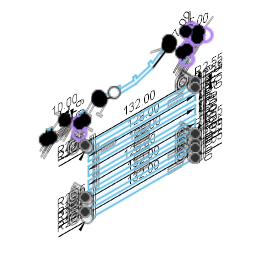
46sp_r2_left (Autodesk Fusion 360 design; units mm, degrees)
Autodesk Fusion 360 part; units mm, degrees
sketch "Sketch_body" plane through (0, 0, 0) normal (1, 0, 0) x (0, 1, 0)
  line L0 (-57.9239, 42.7212) -> (-194.2155, 18.6893)
  line L1 (-28.1683, -14.7541) -> (-42.4304, -4.0068)
  line L2 (-45.4394, -3) -> (-128.1708, -3)
  line L3 (-130.6082, -2.8509) -> (-195.6093, 5.1302)
  arc A0 (-31.8767, 45) -> (-57.9239, 42.7212) centre (-31.8767, -105) ccw
  arc A1 (-28.1683, -14.7541) -> (-25.7686, -15.7236) centre (-25.1592, -10.7609) ccw
  arc A2 (-42.4304, -4.0068) -> (-45.4394, -3) centre (-45.4394, -8) ccw
  arc A3 (-130.6082, -2.8509) -> (-128.1708, -3) centre (-128.1708, 17) ccw
  line L4 (-195.6093, 5.1302) -> (21.9939, -21.5881) construction
  line L5 (-8.7613, -17.8118) -> (-25.7686, -15.7236)
  arc A4 (-8.7613, -17.8118) -> (-3.2843, -13.9917) centre (-8.152, -12.8491) ccw
  line L6 (-195.6093, 5.1302) -> (-197.3656, 5.3459)
  line L7 (-200, 11.7956) -> (-200, 8.3235)
  arc A5 (-200, 8.3235) -> (-197.3656, 5.3459) centre (-197, 8.3235) ccw
  arc A6 (-194.2155, 18.6893) -> (-200, 11.7956) centre (-193, 11.7956) ccw
  line L8 (-31.8767, 45) -> (-2.0562, 45)
  line L9 (-3.2843, -13.9917) -> (7.6792, 32.7148)
  arc A7 (7.6792, 32.7148) -> (-2.0562, 45) centre (-2.0562, 35) ccw
  point P0 (-200, 17.6693)
  point P1 (-200, 5.6693)
  dimension "d171" = 12
  dimension "d216" = 150
  dimension "d218" = 5
  dimension "d219" = 5
  dimension "d220" = 20
  dimension "d229" = 219.2375
  dimension "d230" = 5
  dimension "d233" = 3
  dimension "d234" = 7
  dimension "d263" = 10
  constraint horizontal L2
  constraint tangent L0 A0
  constraint tangent L1 A1
  constraint tangent L2 A2
  constraint tangent L1 A2
  constraint tangent L3 A3
  constraint tangent L2 A3
  constraint coincident P0 L0
  constraint coincident P1 L3
  constraint tangent A1 L5
  constraint tangent L5 A4
  constraint parallel L4 L6
  constraint coincident P1 L6
  constraint tangent L7 A5
  constraint tangent L6 A5
  constraint tangent A0 L8
  constraint horizontal L8
  constraint tangent A4 L9
  constraint tangent L8 A7
  constraint tangent L9 A7
  measures "d171" distance of P0 P1
  measures "d216" radius of A0
  measures "d218" radius of A1
  measures "d219" radius of A2
  measures "d220" radius of A3
  measures "d229" distance of L3.end L4.end
  measures "d230" radius of A4
  measures "d233" radius of A5
  measures "d234" radius of A6
  measures "d263" radius of A7
sketch "Sketch_keypad" plane through (0, 0, 0) normal (1, 0, 0) x (0, 1, 0)
  line L0 (-30, 36.8222) -> (-54.5005, 21.2137)
  line L1 (-54.5005, 21.2137) -> (-52.62, 18.2618)
  line L2 (-28.1195, 33.8704) -> (-30, 36.8222)
  line L3 (-54.5005, 21.2137) -> (-72.6688, 15.4852)
  line L4 (-72.6688, 15.4852) -> (-71.6164, 12.1472)
  line L5 (-71.6164, 12.1472) -> (-53.4481, 17.8757)
  line L6 (-53.4481, 17.8757) -> (-54.5005, 21.2137)
  line L7 (-72.6688, 15.4852) -> (-91.7007, 14.6543)
  line L8 (-91.7007, 14.6543) -> (-91.548, 11.1576)
  line L9 (-91.548, 11.1576) -> (-72.5162, 11.9886)
  line L10 (-72.5162, 11.9886) -> (-72.6688, 15.4852)
  line L11 (-91.7007, 14.6543) -> (-120.0621, 20.9419)
  line L12 (-120.0621, 20.9419) -> (-120.8196, 17.5248)
  line L13 (-120.8196, 17.5248) -> (-92.4582, 11.2373)
  line L14 (-92.4582, 11.2373) -> (-91.7007, 14.6543)
  line L15 (-30, 36.8222) -> (-120.0621, 20.9419) construction
  line L16 (-54.5005, 21.2137) -> (-91.7007, 14.6543) construction
  line L17 (-52.62, 18.2618) -> (-53.4481, 17.8757)
  line L18 (-71.6164, 12.1472) -> (-72.5162, 11.9886)
  line L19 (-91.548, 11.1576) -> (-92.4582, 11.2373)
  line L20 (-120.0621, 20.9419) -> (-115.3589, 37.2783) construction
  line L21 (-30, 36.8222) -> (-39.1341, 51.1599) construction
  line L22 (-39.1341, 51.1599) -> (-115.3589, 37.2783) construction
  line L23 (-72.5162, 11.9886) -> (-71.9927, 0) construction
  line L24 (-71.6164, 12.1472) -> (-68.0079, 0.7026) construction
  line L25 (-68.0079, 0.7026) -> (-71.9927, 0) construction
  circle A0 centre (-53.66, 19.4111) radius 1.55
  circle A1 centre (-72.3235, 13.5266) radius 1.55
  circle A2 centre (-91.874, 12.673) radius 1.55
  line L26 (-30, 36.8222) -> (0, 36.8222) construction
  line L27 (-35.9037, 33.0611) -> (-46.5711, 49.8055) construction
  line L28 (-113.2148, 19.4239) -> (-107.6715, 38.6783) construction
  line L29 (-53.4481, 17.8757) -> (-53.4322, 17.8831)
  line L30 (-28.1195, 33.8704) -> (-52.62, 18.2618)
  circle A3 centre (-31.3073, 35.9894) radius 1.55
  circle A4 centre (-29.4267, 33.0376) radius 1.55
  circle A5 centre (-118.5488, 20.6064) radius 1.55
  circle A6 centre (-119.3064, 17.1894) radius 1.55
  dimension "d15" = 29.05
  dimension "d16" = 3.5
  dimension "d17" = 19.05
  dimension "d18" = 3.5
  dimension "d20" = 3.5
  dimension "d21" = 3.5
  dimension "d22" = 165
  dimension "d23" = 165
  dimension "d24" = 165
  dimension "d26" = 17
  dimension "d27" = 17
  dimension "d28" = 12
  dimension "d30" = 12
  dimension "d37" = 3.1
  dimension "d38" = 3.1
  dimension "d39" = 3.1
  dimension "d56" = 7
  dimension "d58" = 170
  dimension "d85" = 7
  dimension "d90" = 30
  dimension "d270" = 3.1
  dimension "d271" = 3.1
  dimension "d272" = 3.1
  dimension "d273" = 3.1
  constraint perpendicular L0 L1
  constraint parallel L1 L2
  constraint perpendicular L3 L4
  constraint parallel L3 L5
  constraint parallel L4 L6
  constraint perpendicular L7 L8
  constraint parallel L7 L9
  constraint parallel L8 L10
  constraint perpendicular L11 L12
  constraint parallel L11 L13
  constraint parallel L12 L14
  constraint equal L3 L7
  constraint equal L0 L11
  constraint perpendicular L0 L21
  constraint perpendicular L9 L23
  constraint perpendicular L5 L24
  constraint coincident L5.end A0
  constraint coincident L1.end A0
  constraint coincident L9.end A1
  constraint coincident L4.end A1
  constraint coincident L13.end A2
  constraint coincident L8.end A2
  constraint horizontal L26
  constraint coincident L0 L27.start
  constraint coincident L22 L27.end
  constraint perpendicular L0 L27
  constraint coincident L11 L28.start
  constraint coincident L22 L28.end
  constraint parallel L20 L28
  constraint coincident L17 L29.end
  constraint parallel L17 L29
  constraint perpendicular L1 L30
  constraint coincident L0.start A3
  constraint coincident L2.start A4
  constraint coincident L11.end A5
  constraint coincident L12.end A6
  measures "d15" distance of L0.start L0.end
  measures "d16" distance of L0.start L2.start
  measures "d17" distance of L0.end L3.end
  measures "d18" distance of L0.end L5.end
  measures "d20" distance of L3.end L9.end
  measures "d21" distance of L7.end L13.end
  measures "d22" angle of L3 L7
  measures "d23" angle of L0 L3
  measures "d24" angle of L7 L11
  measures "d26" distance of L11.end L20.end
  measures "d27" distance of L0.start L21.end
  measures "d28" distance of L9.end L23.end
  measures "d30" distance of L4.end L24.end
  measures "d37" diameter of A0
  measures "d38" diameter of A1
  measures "d39" diameter of A2
  measures "d56" distance of L21 L27
  measures "d58" angle of L15 L26
  measures "d85" distance of L20 L28
  measures "d90" distance of L0.start L26.end
  measures "d270" diameter of A3
  measures "d271" diameter of A4
  measures "d272" diameter of A5
  measures "d273" diameter of A6
sketch "Sketch_keypad_side" plane through (0, 0, 0) normal (1, 0, 0) x (0, 1, 0)
  line L0 (-28.1195, 33.8704) -> (-30, 36.8222)
  line L1 (-40.3697, 26.0661) -> (-36.6086, 20.1624) construction
  line L2 (-71.6164, 12.1472) -> (-53.4481, 17.8757)
  line L3 (-62.5322, 15.0115) -> (-60.4273, 8.3354) construction
  line L4 (-91.548, 11.1576) -> (-72.5162, 11.9886)
  line L5 (-82.0321, 11.5731) -> (-81.7268, 4.5798) construction
  line L6 (-120.8196, 17.5248) -> (-92.4582, 11.2373)
  line L7 (-106.6389, 14.381) -> (-108.154, 7.547) construction
  line L8 (-36.6086, 20.1624) -> (-23.1195, 28.7559)
  line L9 (-36.6086, 20.1624) -> (-50.0247, 11.6153)
  line L10 (-60.4273, 8.3354) -> (-50.0247, 11.6153)
  line L11 (-60.4273, 8.3354) -> (-70.8298, 5.0555)
  line L12 (-81.7268, 4.5798) -> (-70.8298, 5.0555)
  line L13 (-81.7268, 4.5798) -> (-92.6237, 4.104)
  line L14 (-108.154, 7.547) -> (-92.6237, 4.104)
  line L15 (-108.154, 7.547) -> (-125.8196, 11.4633)
  line L16 (-28.1195, 33.8704) -> (-23.1195, 33.8704) construction
  line L17 (-120.8196, 17.5248) -> (-125.8196, 17.5248) construction
  line L18 (-125.8196, 24.6173) -> (-125.8196, 11.4633)
  line L19 (-30, 36.8222) -> (-120.0621, 20.9419)
  line L20 (-32.6865, 41.0392) -> (-23.1195, 41.0392)
  line L21 (-23.1195, 41.0392) -> (-23.1195, 28.7559)
  line L22 (-32.6865, 41.0392) -> (-125.8196, 24.6173)
  line L23 (-32.6865, 41.0392) -> (83.7533, 41.0392) construction
  line L24 (-92.0091, 11.1289) -> (-92.6237, 4.104) construction
  circle A0 centre (-92.4015, 6.6443) radius 2.55
  line L25 (-72.0543, 12.0001) -> (-70.8298, 5.0555) construction
  circle A1 centre (-71.2726, 7.5668) radius 2.55
  line L26 (-50.0247, 11.6153) -> (-53.034, 18.0688) construction
  circle A2 centre (-51.1024, 13.9264) radius 2.55
  circle A3 centre (-25.6695, 28.7559) radius 2.55
  circle A4 centre (-123.2696, 24.6173) radius 2.55
  circle A5 centre (-123.2696, 11.4633) radius 2.55
  line L27 (-32.6865, 41.0392) -> (-32.242, 35.9586)
  line L28 (-32.6865, 41.0392) -> (-27.5865, 41.0392) construction
  circle A6 centre (-32.4643, 38.4989) radius 2.55
  line L29 (-30, 36.8222) -> (-28.1195, 33.8704)
  line L30 (-30.734, 32.2047) -> (-52.62, 18.2618)
  line L31 (-53.4481, 17.8757) -> (-71.6164, 12.1472)
  line L32 (-72.5162, 11.9886) -> (-91.548, 11.1576)
  line L33 (-92.4582, 11.2373) -> (-117.7931, 16.8539)
  line L34 (-120.0621, 20.9419) -> (-120.8196, 17.5248)
  line L35 (-117.0356, 20.2709) -> (-91.7007, 14.6543)
  line L36 (-91.7007, 14.6543) -> (-72.6688, 15.4852)
  line L37 (-72.6688, 15.4852) -> (-54.5005, 21.2137)
  line L38 (-54.5005, 21.2137) -> (-32.6145, 35.1566)
  arc A7 (-30, 36.8222) -> (-32.6145, 35.1566) centre (-31.3073, 35.9894) ccw
  arc A8 (-30.734, 32.2047) -> (-28.1195, 33.8704) centre (-29.4267, 33.0376) ccw
  arc A9 (-53.4481, 17.8757) -> (-52.62, 18.2618) centre (-53.66, 19.4111) ccw
  arc A10 (-72.5162, 11.9886) -> (-71.6164, 12.1472) centre (-72.3235, 13.5266) ccw
  arc A11 (-92.4582, 11.2373) -> (-91.548, 11.1576) centre (-91.874, 12.673) ccw
  arc A12 (-117.0356, 20.2709) -> (-120.0621, 20.9419) centre (-118.5488, 20.6064) ccw
  arc A13 (-120.8196, 17.5248) -> (-117.7931, 16.8539) centre (-119.3064, 17.1894) ccw
  line L39 (-23.1195, 41.0392) -> (-26.7257, 37.433) construction
  circle A14 centre (-24.9226, 39.2361) radius 2.55
  point P0 (-91.7007, 14.6543)
  point P1 (-72.6688, 15.4852)
  point P2 (-54.5005, 21.2137)
  point P3 (-31.3073, 35.9894)
  point P4 (-29.4267, 33.0376)
  point P5 (-53.66, 19.4111)
  point P6 (-72.3235, 13.5266)
  point P7 (-91.874, 12.673)
  point P8 (-119.3064, 17.1894)
  point P9 (-118.5488, 20.6064)
  dimension "d93" = 7
  dimension "d94" = 7
  dimension "d95" = 7
  dimension "d96" = 7
  dimension "d100" = 5
  dimension "d101" = 5
  dimension "d104" = 5
  dimension "d107" = 170
  dimension "d129" = 5.1
  dimension "d130" = 5.1
  dimension "d131" = 5.1
  dimension "d137" = 5.1
  dimension "d139" = 5.1
  dimension "d140" = 5.1
  dimension "d141" = 85
  dimension "d142" = 5.1
  dimension "d372" = 5.1
  dimension "d373" = 45
  constraint midpoint L2 L3.start
  constraint perpendicular L2 L3
  constraint midpoint L4 L5.start
  constraint perpendicular L4 L5
  constraint midpoint L6 L7.start
  constraint perpendicular L6 L7
  constraint perpendicular L1 L9
  constraint perpendicular L3 L10
  constraint perpendicular L3 L11
  constraint perpendicular L5 L12
  constraint perpendicular L5 L13
  constraint perpendicular L7 L14
  constraint perpendicular L7 L15
  constraint horizontal L16
  constraint coincident L6.start L17.start
  constraint horizontal L17
  constraint horizontal L20
  constraint perpendicular L20 L21
  constraint horizontal L23
  constraint vertical L18
  constraint coincident L4.start L32.end
  constraint coincident L13.end A0
  constraint coincident L11.end A1
  constraint coincident L2.end L31.start
  constraint coincident L9.end A2
  constraint coincident L8.end A3
  constraint coincident L18.start A4
  constraint coincident L15.end A5
  constraint horizontal L28
  constraint coincident L27.end A6
  constraint coincident L20.start A6
  constraint coincident L0.end L19.start
  constraint coincident L30.end A9.end
  constraint coincident L2.start L31.end
  constraint coincident L4.end L32.start
  constraint coincident L6.end L33.start
  constraint coincident L19.end L34.start
  constraint coincident P0 L35.end
  constraint coincident P1 L36.end
  constraint coincident P2 L37.end
  constraint coincident P3 A7.centre
  constraint tangent L0 A7
  constraint coincident P4 A8.centre
  constraint tangent L0 A8
  constraint coincident P5 A9.centre
  constraint coincident P6 A10.centre
  constraint coincident P7 A11.centre
  constraint coincident P8 A13.centre
  constraint coincident P9 A12.centre
  constraint coincident L19.end A12
  constraint coincident A10 L25.start
  constraint coincident A11 L24.start
  constraint coincident L6 L33.end
  constraint coincident L39.end A14
  constraint coincident L20.end A14
  measures "d93" distance of L1.start L1.end
  measures "d94" distance of L3.start L3.end
  measures "d95" distance of L5.start L5.end
  measures "d96" distance of L7.start L7.end
  measures "d100" distance of L0.start L16.end
  measures "d101" distance of L6.start L17.end
  measures "d104" distance of L0.end L20.start
  measures "d107" angle of L22 L23
  measures "d129" diameter of A0
  measures "d130" diameter of A1
  measures "d131" diameter of A2
  measures "d137" diameter of A3
  measures "d139" diameter of A4
  measures "d140" diameter of A5
  measures "d141" angle of L27 L28
  measures "d142" distance of L20.start L27.end
  measures "d372" distance of L20.end L39.end
  measures "d373" angle of L21 L39
extrude "Extrude1" add sketch "Sketch_keypad" along normal mid plane 130 contours L0 A3 | L0 L1 L2 A0 L30 A3 A4 | L30 A4 | L3 L4 L5 L6 A0 A1 | L1 L6 A0 | L1 A0 | L1 L6 L17 A0 L29 | L7 L8 L9 L10 A1 A2 | L4 L10 A1 | L6 A0 | L4 A1 | L4 L10 L18 A1 | L11 L12 L13 L14 A2 A5 A6 | L8 L14 A2 | L10 A1 | L8 A2 | L8 L14 L19 A2 | L11 A5 | L14 A2 | L13 A6 picked at (-30.7698, 35.237) picked at (-29.3326, 33.6055) picked at (-118.8071, 19.7503) picked at (-119.7522, 17.836) makes body 1 in component "keypad"
extrude "Extrude1'" add sketch "Sketch_keypad_side" along normal blind 4 from surface at 60 separate body contours L0 L2 L4 L6 L19 A6 L29 L30 L31 L32 L33 L34 L35 L36 L37 L38 A7 A8 A9 A10 A11 A12 | L0 L2 L4 L6 L8 L9 L10 L11 L12 L13 L14 L15 L18 L19 L20 L21 L22 A0 A1 A2 A3 A4 A5 A6 L29 L30 L31 L32 L33 L34 A7 A8 A9 A10 A11 A12 A13 A14 | L19 A6 A7 | L19 L27 A6 | L19 L27 A6 A7 | L20 L27 A6 A7 | L19 L27 A6 A7 | L19 L27 A7 | L19 L22 L27 A6 A7 | L19 A6 A7 | L19 A6 L35 L36 L37 L38 A7 A12 | L20 L21 A14 | L19 A12 | L22 A4 | L8 A3 | L6 A13 | L15 A5 | L9 L10 A2 | L13 L14 A0 | L11 L12 A1 picked at (-124.0002, 23.7613) picked at (-26.2353, 29.6312) picked at (-122.4553, 11.4729) makes body 2 in component "keypad_side_r"
extrude "Extrude1''" add sketch "Sketch_keypad_side" against normal blind 4 from surface at -60 separate body contours L0 L2 L4 L6 L19 A6 L29 L30 L31 L32 L33 L34 L35 L36 L37 L38 A7 A8 A9 A10 A11 A12 | L0 L2 L4 L6 L8 L9 L10 L11 L12 L13 L14 L15 L18 L19 L20 L21 L22 A0 A1 A2 A3 A4 A5 A6 L29 L30 L31 L32 L33 L34 A7 A8 A9 A10 A11 A12 A13 A14 | L19 A6 A7 | L19 L27 A6 | L19 L27 A6 A7 | L20 L27 A6 A7 | L19 L27 A6 A7 | L19 L27 A7 | L19 L22 L27 A6 A7 | L19 A6 A7 | L19 A6 L35 L36 L37 L38 A7 A12 | L20 L21 A14 | L19 A12 | L22 A4 | L8 A3 | L6 A13 | L15 A5 | L9 L10 A2 | L13 L14 A0 | L11 L12 A1 picked at (-124.0002, 23.7613) picked at (-26.2353, 29.6312) picked at (-122.4553, 11.4729) makes body 3 in component "keypad_side_l"
extrude "Extrude2" cut sketch "Sketch_keypad" along normal through all bodies 2 in component "keypad_side_r"
extrude "Extrude2'" cut sketch "Sketch_keypad" against normal through all bodies 3 in component "keypad_side_l"
extrude "Extrude1'''" add sketch "Sketch_body" along normal blind 12 from surface at 60 separate body makes body 4 in component "body_side_r"
extrude "Extrude1''''" add sketch "Sketch_body" against normal blind 12 from surface at -60 separate body makes body 5 in component "body_side_l"
extrude "Extrude2''" cut sketch "Sketch_keypad_side" against normal blind 6 from surface at -60 contours L0 L2 L4 L6 L19 A6 L29 L30 L31 L32 L33 L34 L35 L36 L37 L38 A7 A8 A9 A10 A11 A12 | L0 L2 L4 L6 L8 L9 L10 L11 L12 L13 L14 L15 L18 L19 L20 L21 L22 A0 A1 A2 A3 A4 A5 A6 L29 L30 L31 L32 L33 L34 A7 A8 A9 A10 A11 A12 A13 A14 | L19 A6 A7 | L19 L27 A6 | L19 L27 A6 A7 | L20 L27 A6 A7 | L19 L27 A6 A7 | L19 L27 A7 | L19 L22 L27 A6 A7 | L19 A6 A7 | L19 A6 L35 L36 L37 L38 A7 A12 | L20 A6 | L22 A6 | L20 A14 | L20 L21 A14 | L19 A12 | L21 A14 | L22 A4 | L22 A4 | L8 A3 | L8 A3 | L6 A13 | L15 A5 | L15 A5 | L9 L10 A2 | L13 L14 A0 | L11 L12 A1 bodies 5 in component "body_side_l"
extrude "Extrude2'''" cut sketch "Sketch_keypad_side" along normal blind 6 from surface at 60 contours L0 L2 L4 L6 L19 A6 L29 L30 L31 L32 L33 L34 L35 L36 L37 L38 A7 A8 A9 A10 A11 A12 | L0 L2 L4 L6 L8 L9 L10 L11 L12 L13 L14 L15 L18 L19 L20 L21 L22 A0 A1 A2 A3 A4 A5 A6 L29 L30 L31 L32 L33 L34 A7 A8 A9 A10 A11 A12 A13 A14 | L19 A6 A7 | L19 L27 A6 | L19 L27 A6 A7 | L20 L27 A6 A7 | L19 L27 A6 A7 | L19 L27 A7 | L19 L22 L27 A6 A7 | L19 A6 A7 | L19 A6 L35 L36 L37 L38 A7 A12 | L20 A6 | L22 A6 | L20 A14 | L20 L21 A14 | L19 A12 | L21 A14 | L22 A4 | L22 A4 | L8 A3 | L8 A3 | L6 A13 | L15 A5 | L15 A5 | L9 L10 A2 | L13 L14 A0 | L11 L12 A1 bodies 4 in component "body_side_r"
sketch "Sketch_inside" plane through (0, 0, 0) normal (1, 0, 0) x (0, 1, 0)
  line L0 (-22.5454, 31.493) -> (-11.2426, 31.493)
  line L1 (-7, 27.2504) -> (-7, 12)
  line L2 (-200, 11.7956) -> (-200, 10.0967)
  line L3 (-195.6052, 5.1335) -> (-193.8472, 4.9191)
  arc A0 (-194.2155, 18.6893) -> (-200, 11.7956) centre (-193, 11.7956) ccw
  arc A1 (-200, 10.0967) -> (-195.6052, 5.1335) centre (-195, 10.0967) ccw
  arc A2 (-159.5313, 0.7351) -> (-147.4283, 0) centre (-147.4283, 100) ccw
  line L4 (-200, 17.6693) -> (-57.9239, 42.7212) construction
  line L5 (-113.2159, 19.4201) -> (-113.2148, 19.4239)
  line L6 (33, 43) -> (-50.411, 43) construction
  line L7 (-10.9159, 43) -> (-29.4045, 43)
  arc A3 (3.5832, 24.1561) -> (-10.9159, 43) centre (-10.9159, 28) ccw
  arc A4 (-29.4045, 43) -> (-35.7906, 33.1332) centre (-29.4045, 36) ccw
  line L8 (-120.8196, 17.5248) -> (-120.0621, 20.9419)
  line L9 (-117.0356, 20.2709) -> (-113.2148, 19.4239)
  line L10 (-113.2148, 19.4238) -> (-113.2148, 19.4239)
  arc A5 (-120.8196, 17.5248) -> (-117.7931, 16.8539) centre (-119.3064, 17.1894) ccw
  arc A6 (-117.0356, 20.2709) -> (-120.0621, 20.9419) centre (-118.5488, 20.6064) ccw
  line L11 (-27, 12) -> (-16, 12)
  line L12 (-10, 12) -> (-7, 12)
  line L13 (-35.7906, 33.1332) -> (-31.8487, 35.6445)
  line L14 (-29.9682, 32.6926) -> (-31.4653, 31.7388)
  line L15 (-30, 36.8222) -> (-30.671, 33.7957) construction
  line L16 (-28.1195, 33.8704) -> (-31.146, 34.5413) construction
  arc A7 (-28.7989, 35.5125) -> (-31.8487, 35.6445) centre (-30.3355, 35.309) ccw
  arc A8 (-29.9682, 32.6926) -> (-28.7989, 35.5125) centre (-29.6327, 34.2059) ccw
  line L17 (-138.8196, 0) -> (-147.4283, 0)
  line L18 (-159.5313, 0.7351) -> (-173.1985, 2.4015)
  line L19 (3.583, 24.1551) -> (3.5832, 24.1561)
  line L20 (-194.2155, 18.6893) -> (-120.7062, 29.0203)
  line L21 (-113.2148, 19.4239) -> (-113.0052, 20.1518)
  arc A9 (-113.0052, 20.1518) -> (-120.7062, 29.0203) centre (-119.732, 22.0885) ccw
  line L22 (-20, 3) -> (-20, -2)
  line L23 (-17, -5) -> (-14.6617, -5)
  arc A10 (-20, -2) -> (-17, -5) centre (-17, -2) ccw
  arc A11 (-14.6617, -5) -> (-0.0565, 6.5812) centre (-14.6617, 10) ccw
  line L24 (-195.6093, 5.1302) -> (21.9939, -21.5881) construction
  line L25 (-27, 12) -> (-27, 3)
  line L26 (2.3012, 18.2936) -> (-0.0565, 6.5812)
  line L27 (2.0211, 16.9023) -> (-7, 18.01)
  line L28 (-7, 12) -> (0.8405, 11.0373)
  line L29 (-127.8196, 3) -> (-127.8196, 0)
  line L30 (-127.8196, 0) -> (-132.8196, 0)
  line L31 (-27, 3) -> (-20, 3)
  line L32 (-27, 3) -> (-120.8196, 3) construction
  line L33 (-120.8196, 10.8902) -> (-120.8196, 3)
  line L34 (-120.8196, 3) -> (-127.8196, 3)
  line L35 (-3.2843, -13.9917) -> (7.6792, 32.7148)
  line L36 (-161.2696, 9) -> (-151.3696, 9)
  line L37 (-148.8196, 11.55) -> (-148.8196, 12.45)
  line L38 (-151.3696, 15) -> (-161.2696, 15)
  line L39 (-163.8196, 12.45) -> (-163.8196, 11.55)
  line L40 (-163.8196, 9) -> (-148.8196, 15) construction
  line L41 (-148.8196, 9) -> (-163.8196, 15) construction
  arc A12 (-148.8196, 12.45) -> (-151.3696, 15) centre (-151.3696, 12.45) ccw
  arc A13 (-151.3696, 9) -> (-148.8196, 11.55) centre (-151.3696, 11.55) ccw
  arc A14 (-161.2696, 15) -> (-163.8196, 12.45) centre (-161.2696, 12.45) ccw
  arc A15 (-163.8196, 11.55) -> (-161.2696, 9) centre (-161.2696, 11.55) ccw
  line L42 (-138.8196, 0) -> (-132.8196, 0)
  line L43 (-132.8196, 0) -> (-132.8196, 10)
  line L44 (-135.3696, 12.55) -> (-136.2696, 12.55)
  line L45 (-138.8196, 10) -> (-138.8196, 0)
  arc A16 (-132.8196, 10) -> (-135.3696, 12.55) centre (-135.3696, 10) ccw
  arc A17 (-136.2696, 12.55) -> (-138.8196, 10) centre (-136.2696, 10) ccw
  line L46 (-132.8196, 0) -> (-138.8196, 0)
  line L47 (-138.8196, 0) -> (-138.8196, -10)
  line L48 (-138.8196, -10) -> (-132.8196, -10)
  line L49 (-132.8196, -10) -> (-132.8196, 0)
  line L50 (-179.1544, 3.1277) -> (-173.1985, 2.4015)
  line L51 (-173.1985, 2.4015) -> (-171.9882, 12.328)
  line L52 (-174.2108, 15.1679) -> (-175.1042, 15.2768)
  line L53 (-177.9441, 13.0542) -> (-179.1544, 3.1277)
  arc A18 (-175.1042, 15.2768) -> (-177.9441, 13.0542) centre (-175.4128, 12.7455) ccw
  arc A19 (-171.9882, 12.328) -> (-174.2108, 15.1679) centre (-174.5194, 12.6366) ccw
  line L54 (-179.1544, 3.1277) -> (-173.1985, 2.4015)
  line L55 (-173.1985, 2.4015) -> (-174.4088, -7.525)
  line L56 (-174.4088, -7.525) -> (-180.3647, -6.7988)
  line L57 (-180.3647, -6.7988) -> (-179.1544, 3.1277)
  line L58 (-179.1544, 3.1277) -> (-193.8472, 4.9191)
  line L59 (3.583, 24.1551) -> (2.3012, 18.2936)
  line L60 (2.3012, 18.2936) -> (-2.5834, 19.3617)
  line L61 (-4.5297, 22.3976) -> (-4.3375, 23.2768)
  line L62 (-1.3016, 25.2232) -> (3.583, 24.1551)
  arc A20 (-1.3016, 25.2232) -> (-4.3375, 23.2768) centre (-1.8463, 22.7321) ccw
  arc A21 (-4.5297, 22.3976) -> (-2.5834, 19.3617) centre (-2.0386, 21.8529) ccw
  line L63 (-10, 12) -> (-16, 12)
  line L64 (-16, 12) -> (-16, 2)
  line L65 (-13.45, -0.55) -> (-12.55, -0.55)
  line L66 (-10, 2) -> (-10, 12)
  arc A22 (-12.55, -0.55) -> (-10, 2) centre (-12.55, 2) ccw
  arc A23 (-16, 2) -> (-13.45, -0.55) centre (-13.45, 2) ccw
  line L67 (-7, 27.2504) -> (-11.2426, 31.493)
  line L68 (-11.2426, 31.493) -> (-8.454, 34.2817)
  line L69 (-4.2113, 30.039) -> (-7, 27.2504)
  line L70 (-5.904, 36.8317) -> (-5.904, 31.7317) construction
  line L71 (-1.6613, 32.589) -> (-6.7613, 32.589) construction
  arc A24 (-4.2113, 30.039) -> (-3.4655, 35.0275) centre (-4.2113, 32.589) ccw
  arc A25 (-3.4655, 35.0275) -> (-8.454, 34.2817) centre (-5.904, 34.2817) ccw
  line L72 (-7, 27.2504) -> (-11.2426, 31.493)
  line L73 (-11.2426, 31.493) -> (-16.1924, 26.5433)
  line L74 (-16.1924, 26.5433) -> (-11.9497, 22.3006)
  line L75 (-11.9497, 22.3006) -> (-7, 27.2504)
  line L76 (-10, 12) -> (-16, 12)
  line L77 (-16, 12) -> (-16, 27)
  line L78 (-16, 27) -> (-10, 27)
  line L79 (-10, 27) -> (-10, 12)
  line L80 (3.583, 24.1551) -> (2.3012, 18.2936)
  line L81 (2.3012, 18.2936) -> (12.0704, 16.1573)
  line L82 (12.0704, 16.1573) -> (13.3521, 22.0188)
  line L83 (13.3521, 22.0188) -> (3.583, 24.1551)
  line L84 (-68.0079, 0.7026) -> (-68.0079, 1)
  line L85 (-120.0621, 20.9419) -> (-72.6688, 15.4852) construction
  line L86 (-72.6688, 15.4852) -> (-77.7808, 31.6984) construction
  line L87 (-71.6164, 12.1472) -> (-68.0079, 0.7026)
  line L88 (-72.6688, 15.4852) -> (-91.7007, 14.6543)
  line L89 (-73.186, 15.4627) -> (-74.5406, 19.7589)
  line L90 (-73.186, 15.4627) -> (-91.7007, 14.6543)
  line L91 (-91.7007, 14.6543) -> (-113.2148, 19.4239)
  line L92 (-119.3304, 29.0885) -> (-80.4159, 24.6081)
  arc A26 (-74.5406, 19.7589) -> (-80.4159, 24.6081) centre (-81.2166, 17.654) ccw
  line L93 (-32.3836, 27.5967) -> (-31.309, 25.91)
  line L94 (-31.309, 25.91) -> (-22.5454, 31.493)
  line L95 (-32.3836, 27.5967) -> (-29.8534, 29.2086)
  line L96 (-29.8534, 29.2086) -> (-31.4653, 31.7388)
  line L97 (-117.7931, 16.8539) -> (-115.8405, 16.421)
  line L98 (-113.561, 12.8428) -> (-113.9938, 10.8902)
  line L99 (-113.9938, 10.8902) -> (-120.8196, 10.8902)
  line L100 (-113.561, 12.8428) -> (-116.4898, 13.4921)
  line L101 (-116.4898, 13.4921) -> (-115.8405, 16.421)
  point P0 (-200, 17.6693)
  point P1 (-120.8196, 17.5248)
  point P2 (-127.8196, 0)
  point P3 (-200, 5.6693)
  point P4 (-57.9239, 42.7212)
  point P5 (-30, 36.8222)
  point P6 (-28.1195, 33.8704)
  point P7 (-156.3196, 12)
  point P8 (-20, -5)
  point P9 (-194.2155, 18.6893)
  point P10 (-156.3196, 12)
  point P11 (-138.8196, 12.55)
  point P12 (-177.6354, 15.5854)
  point P13 (-3.7927, 25.768)
  point P14 (-10, -0.55)
  point P15 (-68.0079, 0.7026)
  point P16 (-72.6688, 15.4852)
  dimension "d169" = 12
  dimension "d235" = 7
  dimension "d236" = 5
  dimension "d237" = 100
  dimension "d261" = 15
  dimension "d262" = 7
  dimension "d290" = 3.1
  dimension "d291" = 3.1
  dimension "d331" = 2
  dimension "d333" = 7
  dimension "d335" = 3
  dimension "d336" = 15
  dimension "d352" = 9
  dimension "d374" = 15
  dimension "d375" = 6
  dimension "d376" = 2.55
  dimension "d377" = 2.55
  dimension "d378" = 2.55
  dimension "d379" = 2.55
  dimension "d380" = 6
  dimension "d381" = 12.55
  dimension "d382" = 2.55
  dimension "d383" = 2.55
  dimension "d384" = 10
  dimension "d385" = 6
  dimension "d386" = 12.55
  dimension "d387" = 2.55
  dimension "d388" = 2.55
  dimension "d389" = 10
  dimension "d390" = 6
  dimension "d391" = 7.55
  dimension "d392" = 2.55
  dimension "d393" = 2.55
  dimension "d396" = 12.55
  dimension "d397" = 2.55
  dimension "d398" = 2.55
  dimension "d399" = 6
  dimension "d402" = 5.1
  dimension "d403" = 5.1
  dimension "d404" = 45
  dimension "d405" = 45
  dimension "d406" = 7
  dimension "d407" = 15
  dimension "d408" = 10
  dimension "d421" = 17
  dimension "d424" = 0.5
  dimension "d425" = 7
  dimension "d462" = 3
  dimension "d467" = 3
  constraint coincident P1 L8.start
  constraint horizontal L0
  constraint perpendicular L1 L11
  constraint coincident P3 L18
  constraint vertical L2
  constraint parallel L3 L18
  constraint tangent L2 A0
  constraint tangent L2 A1
  constraint tangent L3 A1
  constraint tangent A2 L18
  constraint coincident P0 L4.start
  constraint coincident P4 L4.end
  constraint tangent L7 A3
  constraint tangent L7 A4
  constraint coincident L8.end A6.end
  constraint coincident L8.end A6
  constraint coincident P1 A5
  constraint coincident L12.start L11
  constraint collinear L11 L12
  constraint coincident L15.end A7
  constraint coincident P5 A7
  constraint tangent L21 A9
  constraint tangent L20 A9
  constraint perpendicular L22 L23
  constraint coincident P8 L22
  constraint coincident P8 L23
  constraint tangent L22 A10
  constraint tangent L23 A10
  constraint tangent L23 A11
  constraint coincident L1 L27.end
  constraint perpendicular L11 L25
  constraint coincident L26 L27.start
  constraint coincident L26 L28.end
  constraint coincident P2 L29.end
  constraint perpendicular L25 L31
  constraint perpendicular L29 L32
  constraint perpendicular L32 L33
  constraint vertical L33
  constraint horizontal L36
  constraint perpendicular L36 L37
  constraint parallel L36 L38
  constraint parallel L37 L39
  constraint coincident L40 P10
  constraint coincident L41 P10
  constraint coincident P10 P7
  constraint coincident L40.end L38
  constraint coincident L40.end L37
  constraint tangent L38 A12
  constraint tangent L37 A12
  constraint coincident L41.start L36
  constraint coincident L41.start L37
  constraint tangent L36 A13
  constraint tangent L37 A13
  constraint coincident L41.end L38
  constraint coincident L41.end L39
  constraint tangent L38 A14
  constraint tangent L39 A14
  constraint coincident L40.start L39
  constraint coincident L40.start L36
  constraint tangent L39 A15
  constraint tangent L36 A15
  constraint horizontal L42
  constraint vertical L43
  constraint horizontal L44
  constraint vertical L45
  constraint tangent L44 A16
  constraint tangent L43 A16
  constraint coincident P11 L44
  constraint coincident P11 L45
  constraint tangent L44 A17
  constraint tangent L45 A17
  constraint horizontal L46
  constraint vertical L47
  constraint horizontal L48
  constraint vertical L49
  constraint perpendicular L50 L51
  constraint parallel L50 L52
  constraint parallel L51 L53
  constraint coincident P12 L52
  constraint coincident P12 L53
  constraint tangent L52 A18
  constraint tangent L53 A18
  constraint tangent L51 A19
  constraint tangent L52 A19
  constraint perpendicular L54 L55
  constraint parallel L54 L56
  constraint parallel L55 L57
  constraint perpendicular L53 L58
  constraint perpendicular L59 L60
  constraint parallel L59 L61
  constraint parallel L60 L62
  constraint coincident P13 L61
  constraint coincident P13 L62
  constraint tangent L61 A20
  constraint tangent L62 A20
  constraint tangent L60 A21
  constraint tangent L61 A21
  constraint perpendicular L19 L62
  constraint perpendicular L63 L64
  constraint parallel L63 L65
  constraint parallel L64 L66
  constraint coincident P14 L65
  constraint coincident P14 L66
  constraint tangent L65 A22
  constraint tangent L66 A22
  constraint tangent L64 A23
  constraint tangent L65 A23
  constraint vertical L1
  constraint perpendicular L67 L68
  constraint parallel L68 L69
  constraint coincident L70.end A25
  constraint coincident L70.start A25
  constraint perpendicular L72 L73
  constraint parallel L72 L74
  constraint parallel L73 L75
  constraint perpendicular L76 L77
  constraint parallel L76 L78
  constraint parallel L77 L79
  constraint perpendicular L80 L81
  constraint parallel L80 L82
  constraint parallel L81 L83
  constraint coincident P15 L84.start
  constraint perpendicular L32 L84
  constraint coincident P16 L85.end
  constraint parallel L86 L87
  constraint coincident L88 L89.start
  constraint parallel L86 L89
  constraint coincident L88.end L90.end
  constraint parallel L9 L91
  constraint tangent A9 L92
  constraint tangent L89 A26
  constraint tangent L92 A26
  constraint perpendicular L14 L93
  constraint perpendicular L93 L94
  constraint perpendicular L93 L95
  constraint perpendicular L14 L96
  constraint perpendicular L97 L98
  constraint perpendicular L33 L99
  constraint perpendicular L97 L101
  measures "d169" distance of P0 P3
  measures "d235" radius of A0
  measures "d236" radius of A1
  measures "d237" radius of A2
  measures "d261" radius of A3
  measures "d262" radius of A4
  measures "d290" distance of P5 L15.end
  measures "d291" distance of P6 L16.end
  measures "d331" angle of L4 L20
  measures "d333" radius of A9
  measures "d335" radius of A10
  measures "d336" radius of A11
  measures "d352" distance of L11.start L25.end
  measures "d374" distance of L40.end L41.end
  measures "d375" distance of L41.start L40.end
  measures "d376" radius of A12
  measures "d377" radius of A13
  measures "d378" radius of A14
  measures "d379" radius of A15
  measures "d380" distance of L17.start L30.end
  measures "d381" distance of L17.start P11
  measures "d382" radius of A16
  measures "d383" radius of A17
  measures "d384" distance of L30.end L48.end
  measures "d385" distance of L50.start L18.end
  measures "d386" distance of L50.start P12
  measures "d387" radius of A18
  measures "d388" radius of A19
  measures "d389" distance of L50.start L56.end
  measures "d390" distance of L19.start L26.start
  measures "d391" distance of L19.start P13
  measures "d392" radius of A20
  measures "d393" radius of A21
  measures "d396" distance of L12.start P14
  measures "d397" radius of A22
  measures "d398" radius of A23
  measures "d399" distance of L1.start L0.end
  measures "d401" distance of L1.start L71.start
  measures "d402" distance of L70.start L70.end
  measures "d403" distance of L71.start L71.end
  measures "d404" angle of L69 L71
  measures "d405" angle of L68 L70
  measures "d406" distance of L1.start L74.end
  measures "d407" distance of L12.start L78.end
  measures "d408" distance of L19.start L82.end
  measures "d421" distance of P16 L86.end
  measures "d424" distance of L86 L89
  measures "d425" radius of A26
  measures "d462" distance of L93.start L95.end
  measures "d467" distance of L98.start L100.end
extrude "Extrude1'''''" add sketch "Sketch_inside" along normal mid plane 120 separate body contours L0 L1 L7 A3 A4 L13 L14 A7 A8 L26 L27 L60 L61 L62 A20 A21 L68 L69 A24 A25 L93 L94 L95 L96 | L1 L26 L27 L28 | L11 L12 L22 L23 A10 A11 L25 L26 L28 L31 L64 L65 L66 A22 A23 | L2 L3 A0 A1 A2 L8 L9 A5 A6 L17 L18 L20 L21 A9 L29 L30 L33 L34 L43 L44 L45 A16 A17 L51 L52 L53 A18 A19 L58 L97 L98 L99 L100 L101 makes body 6 at (20, 4.0796, 27.6319) makes body 7 at (20, -169.7124, 22.133) in component "inside"
sketch "Sketch_bone" plane through (0, 0, 0) normal (1, 0, 0) x (0, 1, 0)
  line L0 (-11.2426, 31.493) -> (-7, 27.2504)
  line L1 (-7, 27.2504) -> (-2.0503, 32.2001)
  line L2 (-2.0503, 32.2001) -> (-6.2929, 36.4428)
  line L3 (-6.2929, 36.4428) -> (-11.2426, 31.493)
  line L4 (-4.2113, 30.039) -> (-7, 27.2504)
  line L5 (3.583, 24.1551) -> (2.3012, 18.2936)
  line L6 (2.3012, 18.2936) -> (-2.5834, 19.3617)
  line L7 (-2.5834, 19.3617) -> (-1.3016, 25.2232)
  line L8 (-1.3016, 25.2232) -> (3.583, 24.1551)
  line L9 (2.3012, 18.2936) -> (12.0704, 16.1573)
  line L10 (-16, 12) -> (-10, 12)
  line L11 (-10, 12) -> (-10, 2)
  line L12 (-10, 2) -> (-16, 2)
  line L13 (-16, 2) -> (-16, 12)
  line L14 (-10, 2) -> (-10, 12)
  line L15 (-132.8196, 0) -> (-138.8196, 0)
  line L16 (-138.8196, 0) -> (-138.8196, 10)
  line L17 (-138.8196, 10) -> (-132.8196, 10)
  line L18 (-132.8196, 10) -> (-132.8196, 0)
  line L19 (-138.8196, 0) -> (-138.8196, -10)
  line L20 (-173.1985, 2.4015) -> (-179.1544, 3.1277)
  line L21 (-179.1544, 3.1277) -> (-177.9441, 13.0542)
  line L22 (-177.9441, 13.0542) -> (-171.9882, 12.328)
  line L23 (-171.9882, 12.328) -> (-173.1985, 2.4015)
  line L24 (-161.3196, 9) -> (-151.3196, 9)
  line L25 (-151.3196, 9) -> (-151.3196, 15)
  line L26 (-151.3196, 15) -> (-161.3196, 15)
  line L27 (-161.3196, 15) -> (-161.3196, 9)
  line L28 (-161.3196, 9) -> (-151.3196, 15) construction
  line L29 (-151.3196, 9) -> (-161.3196, 15) construction
  line L30 (0, -37.2335) -> (-128, -37.2335)
  line L31 (-128, -37.2335) -> (-128, -45.2335)
  line L32 (-128, -45.2335) -> (0, -45.2335)
  line L33 (0, -45.2335) -> (0, -37.2335)
  line L34 (0, -50.2335) -> (-128, -50.2335)
  line L35 (-128, -50.2335) -> (-128, -60.2335)
  line L36 (-128, -60.2335) -> (0, -60.2335)
  line L37 (0, -60.2335) -> (0, -50.2335)
  line L38 (-2.55, -26.2335) -> (-129.45, -26.2335)
  line L39 (-132, -28.7835) -> (-132, -29.6835)
  line L40 (-129.45, -32.2335) -> (-2.55, -32.2335)
  line L41 (0, -29.6835) -> (0, -28.7835)
  arc A0 (0, -28.7835) -> (-2.55, -26.2335) centre (-2.55, -28.7835) ccw
  arc A1 (-2.55, -32.2335) -> (0, -29.6835) centre (-2.55, -29.6835) ccw
  arc A2 (-129.45, -26.2335) -> (-132, -28.7835) centre (-129.45, -28.7835) ccw
  arc A3 (-132, -29.6835) -> (-129.45, -32.2335) centre (-129.45, -29.6835) ccw
  line L42 (0, -65.2335) -> (-128, -65.2335)
  line L43 (-128, -65.2335) -> (-128, -75.2335)
  line L44 (-128, -75.2335) -> (0, -75.2335)
  line L45 (0, -75.2335) -> (0, -65.2335)
  line L46 (-129.45, -90.2335) -> (-2.55, -90.2335)
  line L47 (-132, -82.7835) -> (-132, -87.6835)
  line L48 (0, -87.6835) -> (0, -82.7835)
  line L49 (-2.55, -80.2335) -> (-129.45, -80.2335)
  line L50 (-2.55, -95.2335) -> (-129.45, -95.2335)
  line L51 (-132, -97.7835) -> (-132, -102.6835)
  line L52 (-129.45, -105.2335) -> (-2.55, -105.2335)
  line L53 (0, -102.6835) -> (0, -97.7835)
  arc A4 (0, -82.7835) -> (-2.55, -80.2335) centre (-2.55, -82.7835) ccw
  arc A5 (-2.55, -90.2335) -> (0, -87.6835) centre (-2.55, -87.6835) ccw
  arc A6 (0, -97.7835) -> (-2.55, -95.2335) centre (-2.55, -97.7835) ccw
  arc A7 (-2.55, -105.2335) -> (0, -102.6835) centre (-2.55, -102.6835) ccw
  arc A8 (-129.45, -95.2335) -> (-132, -97.7835) centre (-129.45, -97.7835) ccw
  arc A9 (-132, -102.6835) -> (-129.45, -105.2335) centre (-129.45, -102.6835) ccw
  arc A10 (-132, -87.6835) -> (-129.45, -90.2335) centre (-129.45, -87.6835) ccw
  arc A11 (-129.45, -80.2335) -> (-132, -82.7835) centre (-129.45, -82.7835) ccw
  line L54 (-97.5279, 10.8965) -> (-96.9498, 10.9218)
  line L55 (-31.4653, 31.7388) -> (-29.8534, 29.2086)
  line L56 (-29.8534, 29.2086) -> (-32.3836, 27.5967)
  line L57 (-32.3836, 27.5967) -> (-31.309, 25.91)
  line L58 (-31.309, 25.91) -> (-50.8773, 13.4436)
  line L59 (-115.8405, 16.421) -> (-116.4898, 13.4921)
  line L60 (-116.4898, 13.4921) -> (-113.561, 12.8428)
  line L61 (-113.561, 12.8428) -> (-113.9938, 10.8902)
  line L62 (-113.9938, 10.8902) -> (-92.4479, 6.1136)
  line L63 (-50.8773, 13.4436) -> (-71.1801, 7.0421)
  line L64 (-71.1801, 7.0421) -> (-92.4479, 6.1136)
  line L65 (-55.9311, 20.7626) -> (-54.8786, 17.4246)
  line L66 (-53.2354, 22.0196) -> (-51.3549, 19.0678)
  line L67 (-53.2354, 22.0196) -> (-55.9311, 20.7626)
  line L68 (-31.4653, 31.7388) -> (-51.3549, 19.0678)
  line L69 (-71.2383, 15.9363) -> (-70.1858, 12.5983)
  line L70 (-74.1674, 15.4198) -> (-74.0147, 11.9231)
  line L71 (-71.2383, 15.9363) -> (-74.1674, 15.4198)
  line L72 (-70.1858, 12.5983) -> (-54.8786, 17.4246)
  line L73 (-90.2021, 14.7197) -> (-90.0495, 11.2231)
  line L74 (-93.1651, 14.979) -> (-93.9227, 11.5619)
  line L75 (-90.2021, 14.7197) -> (-93.1651, 14.979)
  line L76 (-90.0495, 11.2231) -> (-74.0147, 11.9231)
  line L77 (-115.8405, 16.421) -> (-93.9227, 11.5619)
  point P0 (-11.2426, 31.493)
  point P1 (3.583, 24.1551)
  point P2 (2.3012, 18.2936)
  point P3 (-16, 12)
  point P4 (-10, 12)
  point P5 (-132.8196, 0)
  point P6 (-138.8196, 0)
  point P7 (-173.1985, 2.4015)
  point P8 (-179.1544, 3.1277)
  point P9 (-156.3196, 12)
  point P10 (-156.3196, 12)
  point P11 (0, -26.2335)
  point P12 (-132, -26.2335)
  point P13 (0, -32.2335)
  point P14 (0, -90.2335)
  point P15 (0, -80.2335)
  point P16 (-132, -80.2335)
  point P17 (0, -95.2335)
  point P18 (-132, -95.2335)
  point P19 (0, -105.2335)
  point P20 (-29.8534, 29.2086)
  point P21 (-32.3836, 27.5967)
  point P22 (-31.309, 25.91)
  point P23 (-116.4898, 13.4921)
  point P24 (-113.561, 12.8428)
  point P25 (-113.9938, 10.8902)
  dimension "d409" = 7
  dimension "d410" = 5
  dimension "d411" = 10
  dimension "d412" = 6
  dimension "d428" = 128
  dimension "d429" = 8
  dimension "d430" = 128
  dimension "d431" = 10
  dimension "d432" = 5
  dimension "d433" = 132
  dimension "d434" = 6
  dimension "d435" = 2.55
  dimension "d436" = 2.55
  dimension "d437" = 2.55
  dimension "d438" = 2.55
  dimension "d440" = 5
  dimension "d441" = 128
  dimension "d442" = 10
  dimension "d443" = 5
  dimension "d444" = 132
  dimension "d445" = 10
  dimension "d449" = 132
  dimension "d450" = 10
  dimension "d451" = 2.55
  dimension "d452" = 2.55
  dimension "d453" = 2.55
  dimension "d454" = 2.55
  dimension "d455" = 2.55
  dimension "d456" = 2.55
  dimension "d457" = 2.55
  dimension "d458" = 2.55
  constraint perpendicular L0 L1
  constraint parallel L0 L2
  constraint parallel L1 L3
  constraint perpendicular L0 L4
  constraint coincident P0 L0.start
  constraint perpendicular L5 L6
  constraint parallel L5 L7
  constraint parallel L6 L8
  constraint coincident P2 L5.end
  constraint perpendicular L5 L9
  constraint coincident P1 L5.start
  constraint perpendicular L10 L11
  constraint parallel L10 L12
  constraint parallel L11 L13
  constraint coincident P4 L10.end
  constraint perpendicular L10 L14
  constraint coincident P3 L10.start
  constraint perpendicular L15 L16
  constraint parallel L15 L17
  constraint parallel L16 L18
  constraint coincident P6 L15.end
  constraint perpendicular L15 L19
  constraint coincident P5 L15.start
  constraint perpendicular L20 L21
  constraint parallel L20 L22
  constraint parallel L21 L23
  constraint coincident P8 L20.end
  constraint coincident P7 L20.start
  constraint horizontal L24
  constraint perpendicular L24 L25
  constraint parallel L24 L26
  constraint parallel L25 L27
  constraint coincident L28 P10
  constraint coincident L29 P10
  constraint coincident P10 P9
  constraint horizontal L30
  constraint vertical L31
  constraint horizontal L32
  constraint vertical L33
  constraint horizontal L34
  constraint vertical L35
  constraint horizontal L36
  constraint vertical L37
  constraint horizontal L38
  constraint vertical L39
  constraint horizontal L40
  constraint vertical L41
  constraint coincident P11 L38
  constraint coincident P11 L41
  constraint tangent L38 A0
  constraint tangent L41 A0
  constraint coincident P13 L40
  constraint coincident P13 L41
  constraint tangent L40 A1
  constraint tangent L41 A1
  constraint coincident P12 L38
  constraint coincident P12 L39
  constraint tangent L38 A2
  constraint tangent L39 A2
  constraint tangent L39 A3
  constraint tangent L40 A3
  constraint horizontal L42
  constraint vertical L43
  constraint horizontal L44
  constraint vertical L45
  constraint horizontal L49
  constraint vertical L47
  constraint vertical L48
  constraint horizontal L50
  constraint vertical L51
  constraint vertical L53
  constraint coincident P15 L48
  constraint coincident P15 L49
  constraint tangent L48 A4
  constraint tangent L49 A4
  constraint coincident P14 L46
  constraint coincident P14 L48
  constraint tangent L46 A5
  constraint tangent L48 A5
  constraint coincident P17 L50
  constraint coincident P17 L53
  constraint tangent L50 A6
  constraint tangent L53 A6
  constraint coincident P19 L52
  constraint coincident P19 L53
  constraint tangent L52 A7
  constraint tangent L53 A7
  constraint coincident P18 L50
  constraint coincident P18 L51
  constraint tangent L50 A8
  constraint tangent L51 A8
  constraint tangent L51 A9
  constraint tangent L52 A9
  constraint tangent L46 A10
  constraint tangent L47 A10
  constraint coincident P16 L47
  constraint coincident P16 L49
  constraint tangent L47 A11
  constraint tangent L49 A11
  constraint coincident L55.start L68.start
  constraint coincident P20 L55.end
  constraint coincident P21 L56.end
  constraint coincident P22 L57.end
  constraint perpendicular L57 L58
  constraint coincident L59.start L77.start
  constraint coincident P23 L59.end
  constraint coincident P24 L60.end
  constraint coincident P25 L61.end
  constraint perpendicular L59 L62
  measures "d409" distance of P0 L2.end
  measures "d410" distance of P1 L7.end
  measures "d411" distance of L25.end L26.end
  measures "d412" distance of L24.end L25.end
  measures "d428" distance of L30.start L30.end
  measures "d429" distance of L30.start L32.end
  measures "d430" distance of L34.start L34.end
  measures "d431" distance of L34.start L36.end
  measures "d432" distance of L32 L34
  measures "d433" distance of P11 P12
  measures "d434" distance of P11 P13
  measures "d435" radius of A0
  measures "d436" radius of A1
  measures "d437" radius of A2
  measures "d438" radius of A3
  measures "d440" distance of L30 L40
  measures "d441" distance of L42.start L42.end
  measures "d442" distance of L42.start L44.end
  measures "d443" distance of L36 L42
  measures "d444" distance of P15 P16
  measures "d445" distance of P14 P15
  measures "d449" distance of P17 P18
  measures "d450" distance of P17 P19
  measures "d451" radius of A4
  measures "d452" radius of A5
  measures "d453" radius of A6
  measures "d454" radius of A7
  measures "d455" radius of A8
  measures "d456" radius of A9
  measures "d457" radius of A10
  measures "d458" radius of A11
extrude "Extrude1''''''" [rolled back] along distance 128 taper angle 0 in component "bone"
extrude "Extrude3" [rolled back] profile offset 0 along distance -6 taper angle 0 in component "body_side_l"
extrude "Extrude4" [rolled back] profile offset 0 along distance 6 taper angle 0 in component "body_side_r"
component "keypad" placed x (1, 0, 0) y (0, 1, 0) z (0, 0, 1) at (0, 0, 0)
component "keypad_side_r" placed x (1, 0, 0) y (0, 1, 0) z (0, 0, 1) at (0, 0, 0)
component "keypad_side_l" placed x (1, 0, 0) y (0, 1, 0) z (0, 0, 1) at (0, 0, 0)
component "body_side_r" placed x (1, 0, 0) y (0, 1, 0) z (0, 0, 1) at (0, 0, 0)
component "body_side_l" placed x (1, 0, 0) y (0, 1, 0) z (0, 0, 1) at (0, 0, 0)
component "inside" placed x (1, 0, 0) y (0, 1, 0) z (0, 0, 1) at (0, 0, 0)
equation "d15 = 19.05 mm + 3 mm + 7 mm"
equation "d108 = 120 mm + 10 mm"
equation "d141 = ( 170 / 2 ) * 1 deg"
equation "d376 = ( 5.1 / 2 ) * 1 mm"
equation "d377 = ( 5.1 / 2 ) * 1 mm"
equation "d378 = ( 5.1 / 2 ) * 1 mm"
equation "d379 = ( 5.1 / 2 ) * 1 mm"
